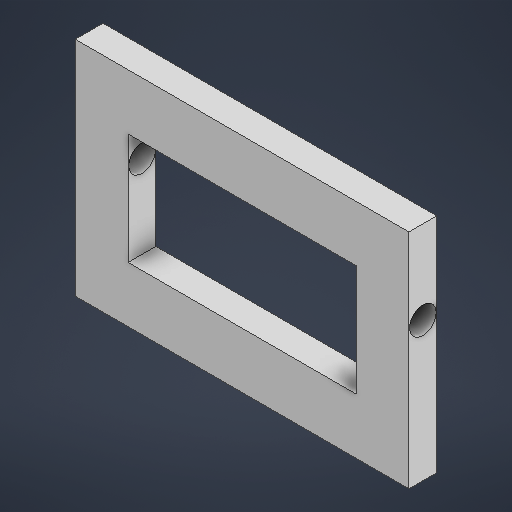
# Autodesk Inventor part: ServoBracket_X
Saved by Autodesk Inventor 2026.2 (Build 302298010, 298A)
## iProperties
Created: 2026-03-09
Part Number: ServoBracket_X
Material: Generic
Document SubType Name: Modeling
Designer: User
Density: 1 g/cm^3
Appearance: Default
Author: User
Autodesk Inventor part; units mm, degrees
ref_plane "YZ Plane" through (0, 0, 0) normal (1, 0, 0) x (0, 1, 0)
ref_plane "XZ Plane" through (0, 0, 0) normal (0, 1, 0) x (-1, 0, 0)
ref_plane "XY Plane" through (0, 0, 0) normal (0, 0, 1) x (1, 0, 0)
sketch "Sketch1" plane through (0, 0, 0) normal (0, 0, 1) x (1, 0, 0)
  line L0 (-27.3928, 17.4379) -> (32.6072, 17.4379)
  line L1 (32.6072, 17.4379) -> (32.6072, -22.5621)
  line L2 (32.6072, -22.5621) -> (-27.3928, -22.5621)
  line L3 (-27.3928, -22.5621) -> (-27.3928, 17.4379)
  point P0 (0, 0)
  dimension "d0" = 60
  dimension "d1" = 40
  constraints: 8 end point, 2 parallel, 1 horizontal, 1 perpendicular
  measures "d0" distance of L0.start L0.end
  measures "d1" distance of L2.end L0.start
extrude "Extrusion1" add sketch "Sketch1" along normal blind 5
sketch "Sketch2" plane through (0, 0, 5) normal (0, 0, 1) x (1, 0, 0)
  line L0 (-17.8928, 7.4379) -> (23.1072, 7.4379)
  line L1 (23.1072, 7.4379) -> (23.1072, -12.5621)
  line L2 (23.1072, -12.5621) -> (-17.8928, -12.5621)
  line L3 (-17.8928, -12.5621) -> (-17.8928, 7.4379)
  line L4 (32.6072, 17.4379) -> (-27.3928, 17.4379) projected
  line L5 (-27.3928, -22.5621) -> (32.6072, -22.5621) projected
  line L6 (32.6072, -22.5621) -> (32.6072, 17.4379) projected
  line L7 (-27.3928, 17.4379) -> (-27.3928, -22.5621) projected
  point P0 (0, 0)
  dimension "d4" = 41
  dimension "d5" = 20
  dimension "d6" = 10
  dimension "d7" = 10
  dimension "d8" = 9.5
  dimension "d9" = 9.5
  constraints: 8 end point, 2 parallel, 1 horizontal, 1 perpendicular
  measures "d4" distance of L0.start L0.end
  measures "d5" distance of L2.end L0.start
  measures "d6" distance between parallel lines of L4 L0
  measures "d7" distance between parallel lines of L5 L2
  measures "d8" distance between parallel lines of L6 L1
  measures "d9" distance between parallel lines of L7 L3
extrude "Extrusion2" cut sketch "Sketch2" against normal through all contours L0 L1 L2 L3
sketch "Sketch3" plane through (32.6072, -22.5621, 0) normal (1, 0, 0) x (0, 0, -1)
  line L0 (-10.2615, 25) -> (11.4979, 25)
  line L1 (0, 40) -> (-5, 40) projected
  line L2 (-2.5, 40) -> (-2.5, -2.7003)
  line L3 (0, 0) -> (0, 40) projected
  line L4 (-5, 0) -> (-5, 40) projected
  circle A0 centre (-2.5, 25) radius 2.4
  point P0 (0, 22.5621)
  dimension "d12" = 2.5
  dimension "d13" = 2.5
  dimension "d14" = 4.8
  dimension "d15" = 15
  constraints: 4 end point, 2 point on line, 1 centre point, 1 horizontal, 1 midpoint, 1 parallel
  measures "d12" distance between parallel lines of L3 L2
  measures "d13" distance between parallel lines of L4 L2
  measures "d14" diameter of A0
  measures "d15" distance from line of L1 A0.centre
extrude "Extrusion3" cut sketch "Sketch3" against normal through all contours A0 L2 L0 | L0 L2 A0 | L2 A0 L0 | L0 A0 L2
body "Solid1"
